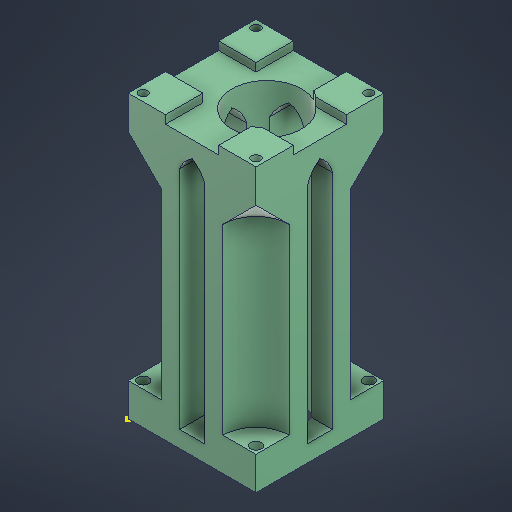
# Autodesk Inventor part: Supports_moteur_pompe
Saved by Autodesk Inventor 2026 (Build 300175000, 175)
## iProperties
Created: 2025-04-28
Part Number: Supports_moteur_pompe
Material: Edelstahl
Document SubType Name: Modeling
Designer: karle
Density: 8 g/cm^3
Appearance: PTFE
Author: karle
Autodesk Inventor part; units mm, degrees
ref_plane "YZ Plane" through (0, 0, 0) normal (1, 0, 0) x (0, 1, 0)
ref_plane "XZ Plane" through (0, 0, 0) normal (0, 1, 0) x (-1, 0, 0)
ref_plane "XY Plane" through (0, 0, 0) normal (0, 0, 1) x (1, 0, 0)
sketch "Skizze1" plane through (0, 0, 0) normal (0, 0, 1) x (1, 0, 0)
  point P0 (0, 0)
sketch "Skizze2" plane through (0, 0, 0) normal (0, 0, 1) x (1, 0, 0)
  line L0 (0, 0) -> (77, 0)
  line L1 (77, 0) -> (77, 77)
  line L2 (77, 77) -> (0, 77)
  line L3 (0, 77) -> (0, 0)
  dimension "d0" = 77
  dimension "d1" = 77
  constraints: 8 end point, 2 parallel, 1 horizontal, 1 perpendicular
  measures "d0" distance of L1.end L2.end
  measures "d1" distance between parallel lines of L0 L2
extrude "Extrusion1" add sketch "Skizze2" along normal blind 170
sketch "Skizze3" plane through (0, 0, 170) normal (0, 0, 1) x (1, 0, 0)
  line L0 (0, 77) -> (0, 0) projected
  line L1 (0, 0) -> (77, 0) projected
  point P0 (4.5, 4.5)
  point P1 (72.5, 4.5)
  point P2 (72.5, 72.5)
  point P3 (4.5, 72.5)
  dimension "d4" = 68
  dimension "d5" = 4.5
  dimension "d6" = 68
  dimension "d7" = 4.5
  constraints: 2 horizontal alignment, 2 vertical alignment
  measures "d4" distance of point (4.5, 72.5) point (72.5, 72.5)
  measures "d5" distance from line of L0 point (4.5, 72.5)
  measures "d6" distance of point (72.5, 4.5) point (72.5, 72.5)
  measures "d7" distance from line of L1 point (4.5, 4.5)
hole "Bohrung1" at (4.5, 72.5, 170) at (4.5, 4.5, 170) at (72.5, 4.5, 170) at (72.5, 72.5, 170) direction (0, 0, -1) diameter 5.3 depth 15
sketch "Skizze4" plane through (0, 0, 170) normal (0, 0, 1) x (1, 0, 0)
  circle A0 centre (45, 38.5) radius 21
  line L0 (0, 77) -> (0, 0) projected
  line L1 (0, 0) -> (77, 0) projected
  point P0 (38.5, 0)
  dimension "d15" = 45
  dimension "d17" = 42
  dimension "d53" = 38.5
  constraints: 1 centre point, 1 midpoint
  measures "d15" distance from line of L0 A0.centre
  measures "d17" diameter of A0
  measures "d53" distance from line of L1 A0.centre
extrude "Extrusion2" cut sketch "Skizze4" against normal through all
sketch "Skizze7" plane through (0, 0, 0) normal (0, 0, -1) x (-1, 0, 0)
  circle A0 centre (-72.5, 4.5) radius 2.65 projected
  circle A1 centre (-72.5, 72.5) radius 2.65 projected
  circle A2 centre (-4.5, 72.5) radius 2.65 projected
  circle A3 centre (-4.5, 4.5) radius 2.65 projected
  point P0 (0, 0)
  constraints: 4 coincident
sketch "Skizze8" plane through (0, 0, 170) normal (0, 0, 1) x (1, 0, 0)
  line L0 (54.5, 77) -> (22.5, 77)
  line L1 (22.5, 77) -> (22.5, 0)
  line L2 (22.5, 0) -> (54.5, 0)
  line L3 (54.5, 0) -> (54.5, 77)
  line L4 (77, 0) -> (77, 77) projected
  line L5 (77, 54.5) -> (0, 54.5)
  line L6 (0, 54.5) -> (0, 22.5)
  line L7 (0, 22.5) -> (77, 22.5)
  line L8 (77, 22.5) -> (77, 54.5)
  line L9 (0, 0) -> (77, 0) projected
  point P0 (22.5, 54.5)
  point P1 (22.5, 22.5)
  point P2 (54.5, 22.5)
  point P3 (54.5, 54.5)
  dimension "d45" = 32
  dimension "d46" = 22.5
  dimension "d47" = 32
  dimension "d48" = 22.5
  dimension "d49" = 77
  dimension "d50" = 77
  constraints: 16 end point, 4 parallel, 3 perpendicular, 2 horizontal, 1 point on line
  measures "d45" distance between parallel lines of L5 L7
  measures "d46" distance between parallel lines of L9 L7
  measures "d47" distance between parallel lines of L3 L1
  measures "d48" distance between parallel lines of L4 L3
  measures "d49" distance between parallel lines of L4 L6
  measures "d50" distance between parallel lines of L0 L9
extrude "Extrusion3" cut sketch "Skizze8" against normal blind 5 contours L3 L5 L1 L0 | L5 L4 L7 L3 | L3 L7 L1 L5 | L1 L7 L6 L5 | L3 L2 L1 L7
hole "Bohrung3" at (72.5, 4.5, 0) at (72.5, 72.5, 0) at (4.5, 72.5, 0) at (4.5, 4.5, 0) direction (0, 0, 1) diameter 6.7 depth 20 tip angle 118
sketch "Skizze9" plane through (77, 77, 0) normal (1, 0, 0) x (0, 0, -1)
  line L0 (0, -77) -> (0, 0) projected
  line L1 (-144.0813, -31) -> (-10, -31)
  line L2 (0, -77) -> (-170, -77) projected
  arc A0 (-155, -38.5) -> (-144.0813, -46) centre (-140.5953, -29.2271) ccw
  arc A1 (-144.0813, -31) -> (-155, -38.5) centre (-140.5953, -47.7729) ccw
  line L3 (-10, -46) -> (-10, -31)
  line L4 (-10, -46) -> (-144.0813, -46)
  line L5 (-165, -22.5) -> (-165, -54.5) projected
  line L6 (-165, -38.5) -> (0, -38.5)
  dimension "d64" = 38.5
  dimension "d65" = 10
  dimension "d66" = 10
  dimension "d74" = 15
  dimension "d75" = 17.1313
  dimension "d76" = 47.7729
  dimension "d77" = 29.2271
  constraints: 8 end point, 4 point on circle, 2 centre point, 2 midpoint, 2 perpendicular, 1 equal radius, 1 horizontal, 1 other
  measures "d64" distance from line of L2 A0.start
  measures "d65" distance from line of L6.end L3
  measures "d66" distance of L6.start A0.start
  measures "d74" distance between parallel lines of L1 L4
  measures "d75" radius of A0
  measures "d76" distance from line of A0.centre L2
  measures "d77" distance from line of A1.centre L2
extrude "Extrusion4" cut sketch "Skizze9" against normal through all
sketch "Skizze10" plane through (0, 77, 0) normal (0, 1, 0) x (1, 0, 0)
  line L0 (22.5, -165) -> (54.5, -165) projected
  line L1 (38.5, -165) -> (38.5, 0)
  line L2 (46, -10) -> (31, -10)
  line L3 (31, -10) -> (31, -146.0265)
  line L4 (46, -10) -> (46, -146.0265)
  line L5 (77, 0) -> (0, 0) projected
  arc A0 (38.5, -155) -> (46, -146.0265) centre (29.895, -140.187) ccw
  arc A1 (31, -146.0265) -> (38.5, -155) centre (47.105, -140.187) ccw
  point P0 (38.5, -10)
  dimension "d87" = 15
  dimension "d88" = 10
  dimension "d89" = 10
  dimension "d90" = 17.131
  dimension "d92" = 0
  dimension "d113" = 140.187
  constraints: 8 end point, 4 point on circle, 2 centre point, 2 midpoint, 2 vertical, 1 horizontal, 1 perpendicular, 1 point on line, 2 other
  measures "d87" distance between parallel lines of L3 L4
  measures "d88" distance between parallel lines of L5 L2
  measures "d89" distance of point (38.5, -165) A0.start
  measures "d90" radius of A1
  measures "d92" distance from line of L1.end L5
  measures "d113" distance from line of L5 A0.centre
extrude "Extrusion5" cut sketch "Skizze10" against normal through all
sketch "Skizze11" plane through (0, 77, 0) normal (0, 1, 0) x (1, 0, 0)
  line L0 (0, -155) -> (0, -144.0813) projected
  line L1 (0, 0) -> (0, -170) projected
  line L2 (0, -150) -> (20, -150)
  line L3 (20, -150) -> (20, -20)
  line L4 (20, -20) -> (0, -20)
  line L5 (77, 0) -> (77, -170) projected
  line L6 (77, -150) -> (57, -150)
  line L7 (57, -150) -> (57, -20)
  line L8 (57, -20) -> (77, -20)
  line L9 (22.5, -165) -> (54.5, -165) projected
  line L10 (38.5, -165) -> (38.5, 0)
  line L11 (24, 0) -> (66, 0) projected
  line L12 (77, 0) -> (0, 0) projected
  line L13 (77, -170) -> (54.5, -170) projected
  point P0 (67, -20)
  point P1 (0, -150)
  point P2 (67, -150)
  dimension "d95" = 20
  dimension "d97" = 20
  dimension "d100" = 20
  constraints: 14 end point, 9 point on line, 3 midpoint, 3 perpendicular, 1 horizontal, 1 vertical, 3 other
  measures "d95" distance between parallel lines of L5 L7
  measures "d97" distance between parallel lines of L12 L8
  measures "d100" distance from line of point (67, -150) L13
revolve "Umdrehung6" cut sketch "Skizze11" angle 360 about axis through (77, 77, 0) along (0, 0, 1) contours L5 L6 L7 L8
revolve "Umdrehung7" cut sketch "Skizze11" angle 360 about axis through (0, 77, 0) along (0, 0, 1) contours L0 L1 L4 L3 L2
sketch "Skizze12" plane through (0, 0, 0) normal (0, -1, 0) x (1, 0, 0)
  line L0 (54.5, 165) -> (22.5, 165) projected
  line L1 (38.5, 165) -> (38.5, 0)
  line L2 (0, 0) -> (0, 170) projected
  line L3 (0, 150) -> (20, 150)
  line L4 (20, 150) -> (20, 20)
  line L5 (20, 20) -> (0, 20)
  line L6 (77, 0) -> (77, 170) projected
  line L7 (77, 20) -> (57, 20)
  line L8 (57, 20) -> (57, 150)
  line L9 (57, 150) -> (77, 150)
  line L10 (0, 170) -> (22.5, 170) projected
  line L11 (0, 0) -> (77, 0) projected
  point P0 (-169.6269, 36.8761)
  point P1 (11.25, 170)
  dimension "d104" = 20
  dimension "d105" = 20
  dimension "d106" = 20
  constraints: 14 end point, 8 point on line, 3 perpendicular, 2 midpoint, 1 horizontal, 1 vertical, 3 other
  measures "d104" distance from line of point (11.25, 170) L3
  measures "d105" distance between parallel lines of L2 L4
  measures "d106" distance between parallel lines of L11 L5
revolve "Umdrehung8" cut sketch "Skizze12" angle 360 about axis through (77, 0, 0) along (0, 0, 1) contours L7 L8 L9 L6
revolve "Umdrehung9" cut sketch "Skizze12" angle 360 about axis through (0, 0, 0) along (0, 0, 1) contours L2 L3 L4 L5
chamfer "Fasen1" distance 20 angle 45 4 edges at (14.1421, 62.8579, 150) (14.1421, 14.1421, 150) (62.8579, 62.8579, 150) (62.8579, 14.1421, 150)
equation "\"d47\" = d45"
